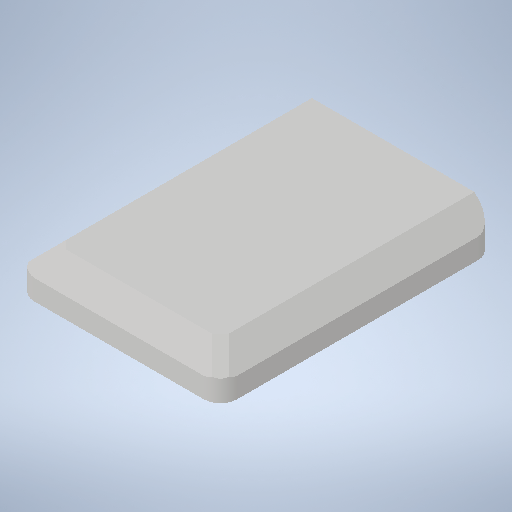
# Autodesk Inventor part: Top Cap Lid
Saved by Autodesk Inventor 2025.2 (Build 292293000, 293)
## iProperties
Created: 2026-07-11
Part Number: Top Cap Lid
Material: Generic
Document SubType Name: Modeling
Designer: crazi
Density: 1 g/cm^3
Appearance: Default
Author: crazi
Autodesk Inventor part; units mm, degrees
ref_plane "YZ Plane" through (0, 0, 0) normal (1, 0, 0) x (0, 1, 0)
ref_plane "XZ Plane" through (0, 0, 0) normal (0, 1, 0) x (-1, 0, 0)
ref_plane "XY Plane" through (0, 0, 0) normal (0, 0, 1) x (1, 0, 0)
sketch "Sketch1" plane through (0, 0, 0) normal (0, 0, 1) x (1, 0, 0)
  line L0 (0, 0) -> (19.9855, 0)
  line L1 (19.9855, 0) -> (22.5145, 0)
  line L2 (19.9855, 0) -> (19.9855, -1.6)
  line L3 (19.9855, -2.8) -> (17.2426, -5.5429)
  line L4 (22.5145, 0) -> (22.5145, -1.6)
  line L5 (22.5145, -2.8) -> (25.2574, -5.5429)
  line L6 (22.5145, -2.8) -> (26.3935, -2.8) construction
  line L7 (17.2426, -5.5429) -> (25.2574, -5.5429)
  line L8 (0, 0) -> (0, -1.7449)
  line L9 (-19.9855, 0) -> (-22.5145, 0)
  line L10 (21.25, -5.5429) -> (21.25, -6.0735)
  line L11 (21.25, -6.0735) -> (24, -6.0735)
  line L12 (21.25, -6.0735) -> (18.5, -6.0735)
  line L13 (18.5, -6.0735) -> (18.5, -4.2855)
  line L14 (18.5, -4.2855) -> (24, -4.2855)
  line L15 (24, -4.2855) -> (24, -6.0735)
  line L16 (18.5, -4.2855) -> (61, -4.2855) construction
  line L17 (21.25, 0) -> (21.25, -1.6)
  line L18 (21.25, -1.6) -> (22.4, -1.6)
  line L19 (21.25, -1.6) -> (20.1, -1.6)
  line L20 (22.5145, -1.6) -> (22.4, -1.6)
  line L21 (19.9855, -1.6) -> (20.1, -1.6)
  line L22 (20.1, -1.6) -> (20.1, -2.6855)
  line L23 (22.4, -1.6) -> (22.4, -2.6855)
  line L24 (19.9855, -2.8) -> (20.1, -2.6855)
  line L25 (22.5145, -2.8) -> (22.4, -2.6855)
  line L26 (-19.9855, 0) -> (-22.5145, 0)
  line L27 (-19.9855, 0) -> (-19.9855, -1.6)
  line L28 (-19.9855, -2.8) -> (-17.2426, -5.5429)
  line L29 (-22.5145, 0) -> (-22.5145, -1.6)
  line L30 (-22.5145, -2.8) -> (-25.2574, -5.5429)
  line L31 (-22.5145, -2.8) -> (-26.3935, -2.8) construction
  line L32 (-17.2426, -5.5429) -> (-25.2574, -5.5429)
  line L33 (-21.25, -5.5429) -> (-21.25, -6.0735)
  line L34 (-21.25, -6.0735) -> (-24, -6.0735)
  line L35 (-21.25, -6.0735) -> (-18.5, -6.0735)
  line L36 (-18.5, -6.0735) -> (-18.5, -4.2855)
  line L37 (-18.5, -4.2855) -> (-24, -4.2855)
  line L38 (-24, -4.2855) -> (-24, -6.0735)
  line L39 (-21.25, 0) -> (-21.25, -1.6)
  line L40 (-21.25, -1.6) -> (-22.4, -1.6)
  line L41 (-21.25, -1.6) -> (-20.1, -1.6)
  line L42 (-22.5145, -1.6) -> (-22.4, -1.6)
  line L43 (-19.9855, -1.6) -> (-20.1, -1.6)
  line L44 (-20.1, -1.6) -> (-20.1, -2.6855)
  line L45 (-22.4, -1.6) -> (-22.4, -2.6855)
  line L46 (-19.9855, -2.8) -> (-20.1, -2.6855)
  line L47 (-22.5145, -2.8) -> (-22.4, -2.6855)
  line L48 (0, 0) -> (-19.9855, 0)
  dimension "d0" = 19.9855
  dimension "d1" = 2.529
  dimension "d2" = 2.8
  dimension "d3" = 3.879
  dimension "d4" = 135
  dimension "d6" = 3.879
  dimension "d7" = 45
  dimension "d8" = 2.8
  dimension "d43" = 2.75
  dimension "d44" = 2.75
  dimension "d49" = 1.6
  dimension "d50" = 1.15
  dimension "d51" = 1.15
  constraints: 98 end point, 21 symmetric about line, 8 vertical, 7 horizontal, 4 perpendicular, 4 point on line, 2 collinear, 2 midpoint, 1 equal length
  measures "d0" distance of L0.start L0.end
  measures "d1" distance of L0.end L1.end
  measures "d2" distance of L0.end L3.start
  measures "d3" distance of L3.start L3.end
  measures "d4" angle of L2 L3
  measures "d6" distance of L5.start L5.end
  measures "d7" angle of L5 L6
  measures "d8" distance of L1.end L5.start
  measures "d43" distance of L10.end L11.end
  measures "d44" distance of L10.end L12.end
  measures "d49" distance of L17.start L17.end
  measures "d50" distance of L17.end L18.end
  measures "d51" distance of L17.end L19.end
extrude "Extrusion1" add sketch "Sketch1" along normal blind 75 contours L1 L17 L19 L21 L2 | L1 L4 L20 L18 L17 | L18 L23 L25 L5 L14 L3 L24 L22 L19 | L27 L43 L41 L39 L9 | L39 L40 L42 L29 L9 | L41 L44 L46 L28 L37 L30 L47 L45 L40
fillet "Fillet1" radius 0.6 4 edges at (24, -4.2855, 37.5) (18.5, -4.2855, 37.5) (-18.5, -4.2855, 37.5) (-24, -4.2855, 37.5)
fillet "Fillet2" radius 0.25 4 edges at (-22.4, -2.6855, 37.5) (-20.1, -2.6855, 37.5) (22.4, -2.6855, 37.5) (20.1, -2.6855, 37.5)
sketch "Sketch2" plane through (-22.5145, 0, 0) normal (0, 1, 0) x (1, 0, 0)
  line L0 (22.5145, 0) -> (52.5145, 0)
  line L1 (52.5145, 0) -> (-7.4855, 0)
  line L2 (-7.4855, 0) -> (-7.4855, -81)
  line L3 (-7.4855, -81) -> (52.5145, -81)
  line L4 (52.5145, -81) -> (52.5145, 0)
  dimension "d13" = 30
  dimension "d14" = 60
  dimension "d15" = 81
  constraints: 10 end point, 2 horizontal, 2 parallel, 1 perpendicular
  measures "d13" distance of L0.start L0.end
  measures "d14" distance of L3.end L2.end
  measures "d15" distance of L2.end L1.end
extrude "Extrusion2" add sketch "Sketch2" along normal blind 12
sketch "Sketch3" plane through (-22.5145, 0, 0) normal (0, -1, 0) x (1, 0, 0)
  line L0 (42.5, 75) -> (42.5, 56)
  line L1 (42.5, 56) -> (41.75, 56)
  line L2 (41.75, 56) -> (41.75, 54.5)
  line L3 (41.75, 54.5) -> (42.5, 54.5)
  line L4 (42.5, 54.5) -> (42.5, 56)
  line L5 (42.5, 54.5) -> (42.5, 52.5)
  line L6 (42.5, 52.5) -> (41.75, 52.5)
  line L7 (41.75, 52.5) -> (41.75, 51)
  line L8 (41.75, 51) -> (42.5, 51)
  line L9 (42.5, 51) -> (42.5, 52.5)
  line L10 (42.5, 51) -> (42.5, 16.438)
  line L11 (42.5, 16.438) -> (41.75, 16.438)
  line L12 (41.75, 16.438) -> (41.75, 14.938)
  line L13 (41.75, 14.938) -> (42.5, 14.938)
  line L14 (42.5, 14.938) -> (42.5, 16.438)
  line L15 (42.5, 14.938) -> (42.5, 12.938)
  line L16 (42.5, 12.938) -> (41.75, 12.938)
  line L17 (41.75, 12.938) -> (41.75, 11.438)
  line L18 (41.75, 11.438) -> (42.5, 11.438)
  line L19 (42.5, 11.438) -> (42.5, 12.938)
  line L20 (22.5145, 0) -> (22.5145, 6.5308)
  line L21 (2.529, 75) -> (2.529, 56)
  line L22 (2.529, 56) -> (3.279, 56)
  line L23 (3.279, 56) -> (3.279, 54.5)
  line L24 (3.279, 54.5) -> (2.529, 54.5)
  line L25 (2.529, 54.5) -> (2.529, 56)
  line L26 (2.529, 54.5) -> (2.529, 52.5)
  line L27 (2.529, 52.5) -> (3.279, 52.5)
  line L28 (3.279, 52.5) -> (3.279, 51)
  line L29 (3.279, 51) -> (2.529, 51)
  line L30 (2.529, 51) -> (2.529, 52.5)
  line L31 (2.529, 51) -> (2.529, 16.438)
  line L32 (2.529, 16.438) -> (3.279, 16.438)
  line L33 (3.279, 16.438) -> (3.279, 14.938)
  line L34 (3.279, 14.938) -> (2.529, 14.938)
  line L35 (2.529, 14.938) -> (2.529, 16.438)
  line L36 (2.529, 14.938) -> (2.529, 12.938)
  line L37 (2.529, 12.938) -> (3.279, 12.938)
  line L38 (3.279, 12.938) -> (3.279, 11.438)
  line L39 (3.279, 11.438) -> (2.529, 11.438)
  line L40 (2.529, 11.438) -> (2.529, 12.938)
  line L41 (45.029, 0) -> (42.5, 0)
  line L42 (43.7645, 0) -> (43.7645, -2.2221)
  line L43 (0, 0) -> (0, 75) projected
  line L44 (2.529, 0) -> (0, 0)
  line L45 (1.2645, 0) -> (1.2645, -2.2221)
  line L46 (45.029, 75) -> (45.029, 56)
  line L47 (45.029, 56) -> (45.779, 56)
  line L48 (45.779, 56) -> (45.779, 54.5)
  line L49 (45.779, 54.5) -> (45.029, 54.5)
  line L50 (45.029, 54.5) -> (45.029, 56)
  line L51 (45.029, 54.5) -> (45.029, 52.5)
  line L52 (45.029, 52.5) -> (45.779, 52.5)
  line L53 (45.779, 52.5) -> (45.779, 51)
  line L54 (45.779, 51) -> (45.029, 51)
  line L55 (45.029, 51) -> (45.029, 52.5)
  line L56 (45.029, 51) -> (45.029, 16.438)
  line L57 (45.029, 16.438) -> (45.779, 16.438)
  line L58 (45.779, 16.438) -> (45.779, 14.938)
  line L59 (45.779, 14.938) -> (45.029, 14.938)
  line L60 (45.029, 14.938) -> (45.029, 16.438)
  line L61 (45.029, 14.938) -> (45.029, 12.938)
  line L62 (45.029, 12.938) -> (45.779, 12.938)
  line L63 (45.779, 12.938) -> (45.779, 11.438)
  line L64 (45.779, 11.438) -> (45.029, 11.438)
  line L65 (45.029, 11.438) -> (45.029, 12.938)
  line L66 (0, 16.438) -> (-0.75, 16.438)
  line L67 (-0.75, 14.938) -> (0, 14.938)
  line L68 (0, 14.938) -> (0, 16.438)
  line L69 (0, 14.938) -> (0, 12.938)
  line L70 (0, 12.938) -> (-0.75, 12.938)
  line L71 (-0.75, 11.438) -> (0, 11.438)
  line L72 (0, 11.438) -> (0, 12.938)
  line L73 (-0.75, 12.938) -> (-0.75, 11.438)
  line L74 (-0.75, 16.438) -> (-0.75, 14.938)
  line L75 (0, 75) -> (0, 56)
  line L76 (0, 51) -> (0, 16.438)
  line L77 (-0.75, 51) -> (0, 51)
  line L78 (-0.75, 52.5) -> (-0.75, 51)
  line L79 (0, 51) -> (0, 52.5)
  line L80 (0, 52.5) -> (-0.75, 52.5)
  line L81 (0, 54.5) -> (0, 52.5)
  line L82 (-0.75, 54.5) -> (0, 54.5)
  line L83 (-0.75, 56) -> (-0.75, 54.5)
  line L84 (0, 56) -> (-0.75, 56)
  line L85 (0, 54.5) -> (0, 56)
  dimension "d18" = 19
  dimension "d19" = 0.75
  dimension "d20" = 1.5
  dimension "d21" = 2
  dimension "d22" = 0.75
  dimension "d23" = 1.5
  dimension "d24" = 34.562
  dimension "d25" = 0.75
  dimension "d26" = 1.5
  dimension "d27" = 2
  dimension "d28" = 0.75
  dimension "d29" = 1.5
  constraints: 170 end point, 50 symmetric about line, 8 parallel, 5 horizontal, 4 perpendicular, 3 vertical, 2 midpoint
  measures "d18" distance of L0.start L0.end
  measures "d19" distance of L3.end L2.end
  measures "d20" distance of L2.end L1.end
  measures "d21" distance of L3.end L5.end
  measures "d22" distance of L8.end L7.end
  measures "d23" distance of L7.end L6.end
  measures "d24" distance of L8.end L10.end
  measures "d25" distance of L13.end L12.end
  measures "d26" distance of L12.end L11.end
  measures "d27" distance of L13.end L15.end
  measures "d28" distance of L18.end L17.end
  measures "d29" distance of L17.end L16.end
extrude "Extrusion3" add sketch "Sketch3" along normal blind 1.6
fillet "Fillet3" radius 0.75 32 edges at (19.2355, -0.8, 11.438) (19.2355, -0.8, 12.938) (19.2355, -0.8, 14.938) (19.2355, -0.8, 16.438) (19.2355, -0.8, 51) (19.2355, -0.8, 52.5) (19.2355, -0.8, 54.5) (19.2355, -0.8, 56) (-23.2645, -0.8, 51) (-23.2645, -0.8, 52.5) (-23.2645, -0.8, 54.5) (-23.2645, -0.8, 56) (-23.2645, -0.8, 11.438) (-23.2645, -0.8, 12.938) (-23.2645, -0.8, 14.938) (-23.2645, -0.8, 16.438) (-19.2355, -0.8, 11.438) (-19.2355, -0.8, 12.938) (-19.2355, -0.8, 14.938) (-19.2355, -0.8, 16.438) (-19.2355, -0.8, 51) (-19.2355, -0.8, 52.5) (-19.2355, -0.8, 54.5) (-19.2355, -0.8, 56) (23.2645, -0.8, 51) (23.2645, -0.8, 52.5) (23.2645, -0.8, 54.5) (23.2645, -0.8, 56) (23.2645, -0.8, 11.438) (23.2645, -0.8, 12.938) (23.2645, -0.8, 14.938) (23.2645, -0.8, 16.438)
fillet "Fillet4" radius 1.25 16 edges at (22.5145, -0.8, 11.438) (22.5145, -0.8, 14.938) (22.5145, -0.8, 12.938) (22.5145, -0.8, 16.438) (22.5145, -0.8, 51) (22.5145, -0.8, 52.5) (22.5145, -0.8, 54.5) (22.5145, -0.8, 56) (19.9855, -0.8, 11.438) (19.9855, -0.8, 12.938) (19.9855, -0.8, 14.938) (19.9855, -0.8, 16.438) (19.9855, -0.8, 51) (19.9855, -0.8, 52.5) (19.9855, -0.8, 54.5) (19.9855, -0.8, 56)
sketch "Sketch4" plane through (-22.5145, 0, 0) normal (0, -1, 0) x (1, 0, 0)
  line L0 (42.5, 0) -> (42.5, 10.6268) projected
  line L1 (42.5, 0) -> (40.015, 0)
  line L2 (42.5, 0) -> (2.529, 0) projected
  line L3 (2.529, 0) -> (5.014, 0)
  line L4 (40.015, 0) -> (3.7715, 0)
  line L5 (3.7715, 0) -> (3.7715, 75)
  line L6 (3.7715, 75) -> (40.015, 75)
  line L7 (40.015, 75) -> (40.015, 0)
  line L8 (42.5, 75) -> (40.015, 75)
  point P0 (22.5145, 0)
  dimension "d34" = 2.485
  dimension "d35" = 2.485
  dimension "d36" = 75
  constraints: 14 end point, 2 horizontal, 2 parallel, 2 point on line, 1 perpendicular
  measures "d34" distance of L0.start L1.end
  measures "d35" distance of L2.end L3.end
  measures "d36" distance of L4.end L5.end
extrude "Extrusion4" cut sketch "Sketch4" against normal blind 7
chamfer "Chamfer1" distance 6 angle 45 6 edges at (30, 12, 40.5) (0, 12, 81) (-30, 12, 40.5) (-18.743, 7, 37.5) (-0.6212, 7, 75) (17.5005, 7, 37.5)
fillet "Fillet5" radius 5 4 edges at (-30, 3, 0) (-30, 3, 81) (30, 3, 81) (30, 3, 0)
chamfer "Chamfer2" distance 2 angle 45 2 edges at (26.2678, 9.7322, 77.2678) (-26.2678, 9.7322, 77.2678)
body "Solid1"
